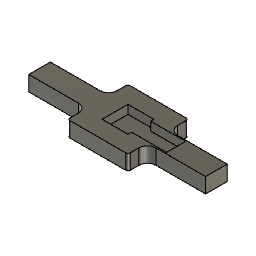
ec11 holder v1 (Autodesk Fusion 360 design; units mm, degrees)
Autodesk Fusion 360 part; units mm, degrees
sketch "Sketch1" plane through (0, 0, 0) normal (0, 0, 1) x (1, 0, 0)
  line L0 (6, 6) -> (-6, 6)
  line L1 (-6, 6) -> (-6, -6)
  line L2 (-6, -6) -> (6, -6)
  line L3 (6, -6) -> (6, 6)
  line L4 (6, 6) -> (-6, -6) construction
  line L5 (-6, 6) -> (6, -6) construction
  line L6 (13, 14) -> (-13, 14)
  line L7 (-13, -14) -> (13, -14)
  line L8 (14, 14) -> (-14, -14) construction
  line L9 (-14, 14) -> (14, -14) construction
  line L10 (0, 0) -> (-6, 0)
  line L11 (-41, 0) -> (-41, 5)
  line L12 (-41, 5) -> (-18, 5)
  line L13 (-41, 0) -> (-41, -5)
  line L14 (-41, -5) -> (-18, -5)
  line L15 (41, 0) -> (41, -5)
  line L16 (41, -5) -> (18, -5)
  line L17 (41, 0) -> (41, 5)
  line L18 (41, 5) -> (18, 5)
  line L19 (-14, 13) -> (-14, 9)
  line L20 (-14, -9) -> (-14, -13)
  line L21 (0, 0) -> (6, 0)
  line L22 (14, -13) -> (14, -9)
  line L23 (14, 9) -> (14, 13)
  arc A0 (-18, 5) -> (-14, 9) centre (-18, 9) ccw
  arc A1 (14, 9) -> (18, 5) centre (18, 9) ccw
  arc A2 (18, -5) -> (14, -9) centre (18, -9) ccw
  arc A3 (-14, -9) -> (-18, -5) centre (-18, -9) ccw
  arc A4 (-13, 14) -> (-14, 13) centre (-13, 13) ccw
  arc A5 (14, 13) -> (13, 14) centre (13, 13) ccw
  arc A6 (-14, -13) -> (-13, -14) centre (-13, -13) ccw
  arc A7 (13, -14) -> (14, -13) centre (13, -13) ccw
  dimension "d1" = 4
  dimension "d2" = 1
  constraint horizontal L0
  constraint perpendicular L0 L1
  constraint parallel L0 L2
  constraint parallel L1 L3
  constraint coincident L4 L10.start
  constraint coincident L5 L10.start
  constraint coincident L10.start L21.start
  constraint horizontal L6
  constraint perpendicular L6 L19
  constraint parallel L6 L7
  constraint parallel L19 L22
  constraint coincident L8 L10.start
  constraint coincident L9 L10.start
  constraint horizontal L21
  constraint perpendicular L10 L19
  constraint perpendicular L10 L11
  constraint perpendicular L12 L19
  constraint perpendicular L10 L13
  constraint perpendicular L14 L19
  constraint perpendicular L15 L21
  constraint perpendicular L16 L22
  constraint perpendicular L17 L21
  constraint perpendicular L18 L22
  constraint collinear L19 L20
  constraint coincident L1 L10.end
  constraint coincident L3 L21.end
  constraint collinear L22 L23
  constraint tangent L12 A0
  constraint tangent L19 A0
  constraint tangent L18 A1
  constraint tangent L23 A1
  constraint equal A0 A1
  constraint tangent L16 A2
  constraint tangent L22 A2
  constraint equal A0 A2
  constraint tangent L14 A3
  constraint tangent L20 A3
  constraint equal A0 A3
  constraint coincident L9.start L19
  constraint coincident L9.start L6
  constraint tangent L19 A4
  constraint tangent L6 A4
  constraint coincident L8.start L6
  constraint coincident L8.start L23
  constraint tangent L6 A5
  constraint tangent L23 A5
  constraint equal A4 A5
  constraint coincident L8.end L7
  constraint coincident L8.end L20
  constraint tangent L7 A6
  constraint tangent L20 A6
  constraint equal A4 A6
  constraint coincident L9.end L7
  constraint coincident L9.end L22
  constraint tangent L7 A7
  constraint tangent L22 A7
  constraint equal A4 A7
  measures "d1" radius of A0
  measures "d2" radius of A4
extrude "Extrude1" add sketch "Sketch1" along normal blind 7
box "BoxPrimitive1" add length 12 width 12 height 3 placed x (0, 1, 0) y (-1, 0, 0) z (0, 0, 1) at (6, -6, 0)
sketch "Sketch3" plane through (0, 0, 7) normal (0, 0, 1) x (-1, 0, 0)
  line L0 (-6, -6) -> (-6, 6)
  line L1 (-6, 6) -> (6, 6)
  line L2 (6, 6) -> (6, -6)
  line L3 (6, -6) -> (-6, -6)
  line L4 (14, 9) -> (14, 13)
  arc A0 (14, 13) -> (13, 14) centre (13, 13) ccw
  line L5 (13, 14) -> (-13, 14)
  arc A1 (-13, 14) -> (-14, 13) centre (-13, 13) ccw
  line L6 (-14, 13) -> (-14, 9)
  arc A2 (-18, 5) -> (-14, 9) centre (-18, 9) ccw
  line L7 (-18, 5) -> (-41, 5)
  line L8 (-41, 5) -> (-41, -5)
  line L9 (-41, -5) -> (-18, -5)
  arc A3 (-14, -9) -> (-18, -5) centre (-18, -9) ccw
  line L10 (-14, -9) -> (-14, -13)
  arc A4 (-14, -13) -> (-13, -14) centre (-13, -13) ccw
  line L11 (-13, -14) -> (13, -14)
  arc A5 (13, -14) -> (14, -13) centre (13, -13) ccw
  line L12 (14, -13) -> (14, -9)
  arc A6 (18, -5) -> (14, -9) centre (18, -9) ccw
  line L13 (18, -5) -> (41, -5)
  line L14 (41, -5) -> (41, 5)
  line L15 (41, 5) -> (18, 5)
  arc A7 (14, 9) -> (18, 5) centre (18, 9) ccw
  line L16 (-6, 0) -> (-6, -4.5)
  line L17 (-6, -4.5) -> (-18.2418, -4.5)
  line L18 (-18.2418, -4.5) -> (-18.2418, 4.3399)
  line L19 (-18.2418, 4.3399) -> (-6, 4.3399)
  line L20 (-6, 4.3399) -> (-6, -4.5)
  constraint midpoint L0 L16.start
  constraint coincident L0 L16.end
  constraint horizontal L17
  constraint vertical L18
  constraint horizontal L19
  constraint vertical L20
extrude "Extrude2" cut sketch "Sketch3" against normal blind 4 contours L0 L16 L17 L18 L19 L20
chamfer "Chamfer1" distance 4 angle 45 1 edges at (18.2418, 0.08, 7)
